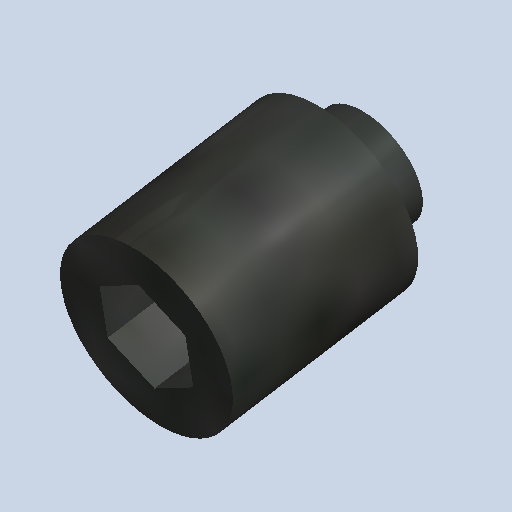
# Autodesk Inventor part: Prisionero_M3x4
Saved by Autodesk Inventor 2025.3 (Build 293356000, 356)
## iProperties
Part Number: Prisionero_M3x4
Material: Acero
Document SubType Name: Modelado
Designer: STEVEN LONDOÑO
Density: 7.85 g/cm^3
Appearance: Placa
Author: STEVEN LONDOÑO
Autodesk Inventor part; units mm, degrees
ref_plane "Plano YZ" through (0, 0, 0) normal (1, 0, 0) x (0, 1, 0)
ref_plane "Punta que asienta sobre el plano D" through (114.254, -0.2427, 1.4802) normal (0, -0.1617885, 0.9868255) x (0, -0.9868255, -0.1617885)
sketch "Boceto1" plane through (114.254, -0.2427, 1.4802) normal (0, -0.1617885, 0.9868255) x (0, -0.9868255, -0.1617885)
  circle A0 centre (0, 0) radius 0.9
  constraints: 1 centre point
extrude "Punta plana de contacto" add sketch "Boceto1" along normal blind 0.7
ref_plane "Plano de trabajo2" through (114.254, -0.3559, 2.171) normal (0, -0.1617885, 0.9868255) x (0, -0.9868255, -0.1617885)
sketch "Boceto2" plane through (114.254, -0.3559, 2.171) normal (0, -0.1617885, 0.9868255) x (0, -0.9868255, -0.1617885)
  circle A0 centre (0, 0) radius 1.5
  constraints: 1 centre point
extrude "Envolvente nominal M3" add sketch "Boceto2" along normal blind 3.3
ref_plane "Plano de trabajo3" through (114.254, -0.8898, 5.4275) normal (0, -0.1617885, 0.9868255) x (0, -0.9868255, -0.1617885)
sketch "Boceto3" plane through (114.254, -0.8898, 5.4275) normal (0, -0.1617885, 0.9868255) x (0, -0.9868255, -0.1617885)
  line L0 (0.87, 0) -> (0.435, 0.7534)
  line L1 (0.435, 0.7534) -> (-0.435, 0.7534)
  line L2 (-0.435, 0.7534) -> (-0.87, 0)
  line L3 (-0.87, 0) -> (-0.435, -0.7534)
  line L4 (-0.435, -0.7534) -> (0.435, -0.7534)
  line L5 (0.435, -0.7534) -> (0.87, 0)
  constraints: 12 end point
extrude "Acceso hexagonal provisional" cut sketch "Boceto3" against normal blind 1.3
